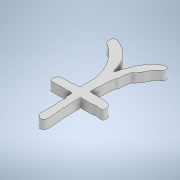
# Autodesk Inventor part: asterisk
Saved by Autodesk Inventor 2022.6 (Build 266554000, 554)
## iProperties
Created: 2024-11-29
Part Number: asterisk
Material: Generic
Document SubType Name: Modeling
Designer: Dragos Macovei
Density: 1 g/cm^3
Appearance: Default
Author: Dragos Macovei
Autodesk Inventor part; units mm, degrees
ref_plane "YZ Plane" through (0, 0, 0) normal (1, 0, 0) x (0, 1, 0)
ref_plane "XZ Plane" through (0, 0, 0) normal (0, 1, 0) x (-1, 0, 0)
ref_plane "XY Plane" through (0, 0, 0) normal (0, 0, 1) x (1, 0, 0)
sketch "Sketch1" plane through (0, 0, 0) normal (0, 1, 0) x (-1, 0, 0)
  line L0 (0, 0) -> (40, 0)
  line L1 (40, 0) -> (40, 40)
  line L2 (40, 40) -> (0, 40)
  line L3 (0, 40) -> (0, 0)
  line L4 (-196.3315, 239.7568) -> (210.0685, 239.7568) construction
  line L5 (210.0685, 239.7568) -> (210.0685, -302.1099) construction
  line L6 (210.0685, -302.1099) -> (-196.3315, -302.1099) construction
  line L7 (-196.3315, -302.1099) -> (-196.3315, 239.7568) construction
  spline S0 degree 5 poles (20.2281, 27.3819) (20.2569, 27.204) (20.2549, 26.8723) (20.134, 26.258) (20.1988, 25.9402) (20.624, 25.3677) (20.8566, 25.5249) (22.1402, 25.6276) (22.1374, 25.5328) (23.2908, 25.585) (23.6528, 25.43) (24.9068, 25.6468) (25.0732, 25.5218) (26.0735, 25.6479) (26.7605, 25.418) (27.4178, 25.7195) (27.6592, 25.3157) (27.8745, 24.8663) (27.9029, 24.2265) (27.5396, 23.4329) (27.123, 22.9859) (26.2982, 22.585) (25.8641, 22.9911) (24.6164, 22.6411) (24.2692, 22.8677) (23.501, 22.8137) (23.173, 22.7419) (21.6956, 22.4064) (21.6055, 22.7926) (20.1295, 22.4021) (21.1477, 21.1629) (20.6367, 20.4244) (20.7369, 18.6844) (20.8421, 18.3965) (20.7675, 16.6239) (21.1918, 16.2838) (21.3546, 14.7956) (21.8177, 14.0398) (22.0249, 12.759) (22.879, 11.999) (23.0894, 10.8923) (24.5043, 9.4106) (24.6383, 9.1741) (25.697, 7.9506) (26.2305, 7.4611) (26.9373, 6.6722) (27.6755, 6.2368) (28.2347, 5.9023) (28.9131, 5.4341) (29.3549, 5.1414) (29.401, 4.182) (29.338, 2.8435) (28.7401, 2.938) (27.7646, 2.6447) (27.5697, 3.1148) (26.9975, 3.3775) (26.2713, 3.4322) (26.1961, 3.6335) (25.4895, 4.1035) (25.3274, 4.0249) (24.6635, 4.7365) (24.3187, 4.6533) (23.6375, 5.2769) (23.5581, 5.6382) (22.7165, 6.1613) (22.6355, 6.5113) (21.9199, 6.8836) (21.8943, 7.4091) (21.3956, 7.9206) (21.3458, 8.3927) (20.9019, 8.991) (20.5693, 9.7122) (20.5501, 10.0411) (19.9364, 10.9466) (20.1159, 11.2294) (19.8317, 11.6297) (19.8411, 11.9953) (19.8532, 12.3537) (19.4882, 12.5146) (19.194, 12.072) (19.0966, 11.5108) (18.7825, 9.7025) (17.5682, 8.2623) (17.9054, 7.6693) (17.2705, 6.4082) (16.9669, 6.6229) (15.9508, 3.9967) (15.5021, 4.5029) (15.5187, 3.5212) (14.0905, 3.4108) (14.4439, 2.8232) (13.1534, 2.6958) (13.3925, 2.2878) (12.3471, 2.4244) (12.1262, 2.0127) (11.5009, 2.6744) (11.5881, 2.8407) (11.4434, 3.5926) (11.5846, 3.8117) (12.0443, 4.3221) (12.4856, 4.3681) (13.1431, 5.2994) (13.3385, 5.2237) (13.904, 6.3946) (14.2262, 7.085) (14.6864, 7.9895) (15.408, 8.4489) (15.5208, 9.5486) (16.5448, 9.489) (16.3687, 10.3446) (16.7009, 11.0947) (16.8321, 11.9735) (16.8069, 12.7968) (16.7762, 13.9207) (17.5294, 14.1797) (17.1249, 15.2812) (17.8431, 16.4185) (17.3602, 17.8771) (17.6668, 19.3644) (17.7503, 19.7363) (17.7277, 21.2778) (17.7746, 21.6575) (17.7621, 22.5836) (17.2166, 21.8598) (16.3217, 22.5022) (16.1361, 22.1284) (15.5326, 22.3347) (15.0782, 22.2459) (14.4673, 22.2409) (13.8289, 22.2946) (13.217, 22.283) (12.6504, 22.3687) (12.2721, 22.3558) (11.6957, 22.4418) (11.29, 22.5947) (10.8897, 22.9545) (10.5951, 23.1648) (10.1899, 23.6221) (10.1568, 24.2264) (10.2703, 24.5188) (10.0556, 25.317) (10.9444, 25.3035) (11.3109, 25.529) (12.24, 25.157) (13.047, 25.0781) (13.4217, 25.4312) (14.3351, 25.3205) (14.6439, 25.4533) (15.6247, 25.4451) (16.333, 25.3555) (16.9826, 25.5786) (17.8706, 25.1233) (17.5778, 25.9282) (17.6271, 26.571) (17.6972, 27.6801) (17.5119, 28.2924) (17.5903, 29.2013) (17.5123, 29.8826) (17.4935, 30.751) (17.5747, 32.0925) (17.2728, 32.1531) (17.4079, 33.4982) (17.271, 33.8972) (17.0965, 34.9435) (17.3021, 35.6483) (16.9283, 36.0539) (17.1812, 36.9191) (17.1135, 37.5927) (17.662, 37.9269) (17.9732, 38.1164) (18.6653, 38.3873) (18.7158, 37.6968) (19.2912, 37.486) (19.7103, 37.5451) (19.7738, 36.726) (19.9154, 36.2269) (19.8471, 34.3604) (19.8424, 33.7251) (19.6141, 31.1217) (20.4021, 30.6965) (19.6151, 28.1403) (20.047, 27.9061) (20.1923, 27.6029) (20.2281, 27.3819) knots 0 0 0 0 0 0 0.006822 0.010789 0.016049 0.020854 0.025832 0.031113 0.036873 0.042272 0.048016 0.05382 0.059393 0.064443 0.069443 0.074258 0.079073 0.084102 0.08948 0.095068 0.100968 0.106627 0.112101 0.117494 0.123209 0.128587 0.134095 0.139902 0.146101 0.152454 0.159003 0.165913 0.172773 0.179651 0.186334 0.19322 0.200017 0.207151 0.214553 0.221755 0.229012 0.236195 0.243157 0.249633 0.256028 0.262055 0.26774 0.273408 0.279255 0.285053 0.290881 0.296629 0.302123 0.307232 0.312077 0.3168 0.321442 0.326114 0.330747 0.335687 0.340634 0.345934 0.351094 0.356315 0.36142 0.366531 0.371441 0.376541 0.381753 0.387018 0.39248 0.397786 0.402788 0.407462 0.411797 0.415501 0.419062 0.422732 0.427418 0.433305 0.439817 0.446827 0.454047 0.461339 0.467524 0.473502 0.479619 0.485504 0.490638 0.495749 0.500948 0.505749 0.510597 0.515091 0.519803 0.524224 0.528692 0.533208 0.538137 0.542965 0.548254 0.553974 0.56 0.5661 0.572535 0.578735 0.584554 0.590277 0.595993 0.601813 0.607854 0.613898 0.619875 0.626102 0.632759 0.639686 0.64684 0.654283 0.661273 0.667235 0.672555 0.677858 0.682509 0.68698 0.691677 0.696531 0.701292 0.706341 0.711459 0.716495 0.721451 0.726206 0.730794 0.735292 0.739925 0.744571 0.749167 0.753799 0.758532 0.763291 0.768367 0.773759 0.779187 0.784726 0.790187 0.795596 0.801055 0.806706 0.812154 0.8174 0.822595 0.827942 0.833302 0.838963 0.845014 0.851231 0.857421 0.863348 0.869377 0.875408 0.881386 0.887101 0.892841 0.898502 0.904111 0.909365 0.914458 0.91949 0.924251 0.92887 0.93332 0.937696 0.942277 0.947501 0.95338 0.960404 0.968319 0.976932 0.985024 0.991521 1 1 1 1 1 1
  point P0 (20.3136, 25.8438)
  point P1 (20.5822, 25.5356)
  point P2 (20.9377, 25.4961)
  point P3 (21.8779, 25.583)
  point P4 (22.3124, 25.5672)
  point P5 (23.0709, 25.5435)
  point P6 (23.8214, 25.5119)
  point P7 (24.7379, 25.5751)
  point P8 (25.2277, 25.5751)
  point P9 (26.0731, 25.5672)
  point P10 (26.9105, 25.5435)
  point P11 (27.3924, 25.5435)
  point P12 (27.6295, 25.3302)
  point P13 (27.8033, 24.9273)
  point P14 (27.8349, 24.319)
  point P15 (27.5347, 23.5368)
  point P16 (27.029, 23.0075)
  point P17 (26.3891, 22.7704)
  point P18 (25.7175, 22.8258)
  point P19 (24.6905, 22.7625)
  point P20 (24.1532, 22.81)
  point P21 (23.6397, 22.81)
  point P22 (23.063, 22.7151)
  point P23 (21.9411, 22.565)
  point P24 (21.3643, 22.6124)
  point P25 (20.7402, 22.3122)
  point P26 (20.7797, 21.4274)
  point P27 (20.7797, 20.3055)
  point P28 (20.7481, 18.915)
  point P29 (20.8034, 18.0933)
  point P30 (20.8903, 16.8767)
  point P31 (21.1194, 16.0945)
  point P32 (21.4117, 14.9805)
  point P33 (21.7515, 13.9693)
  point P34 (22.1465, 12.9185)
  point P35 (22.6995, 11.9941)
  point P36 (23.3474, 10.8249)
  point P37 (24.3466, 9.5465)
  point P38 (24.8487, 8.9487)
  point P39 (25.6497, 8.0402)
  point P40 (26.3192, 7.3468)
  point P41 (27.0365, 6.6773)
  point P42 (27.7179, 6.2111)
  point P43 (28.2917, 5.8524)
  point P44 (28.8536, 5.4698)
  point P45 (29.2123, 5.0873)
  point P46 (29.3677, 4.1429)
  point P47 (29.1405, 3.0789)
  point P48 (28.5667, 2.8517)
  point P49 (27.8494, 2.8398)
  point P50 (27.4788, 3.0789)
  point P51 (26.9169, 3.3419)
  point P52 (26.367, 3.4853)
  point P53 (26.0801, 3.6766)
  point P54 (25.6019, 3.9874)
  point P55 (25.2791, 4.1548)
  point P56 (24.7531, 4.5493)
  point P57 (24.2868, 4.7884)
  point P58 (23.7728, 5.2188)
  point P59 (23.4022, 5.6611)
  point P60 (22.8403, 6.1632)
  point P61 (22.4936, 6.5219)
  point P62 (22.0632, 6.9284)
  point P63 (21.8002, 7.3946)
  point P64 (21.5013, 7.8967)
  point P65 (21.2861, 8.3629)
  point P66 (20.9394, 8.9966)
  point P67 (20.6286, 9.6541)
  point P68 (20.4015, 10.204)
  point P69 (20.0665, 10.9668)
  point P70 (20, 11.3199)
  point P71 (19.8773, 11.6857)
  point P72 (19.8394, 12.0515)
  point P73 (19.7701, 12.31)
  point P74 (19.5998, 12.3983)
  point P75 (19.3854, 12.2848)
  point P76 (19.1773, 11.837)
  point P77 (18.6814, 10.0278)
  point P78 (17.8311, 8.2007)
  point P79 (17.6557, 7.3951)
  point P80 (17.3291, 6.7206)
  point P81 (16.883, 6.1285)
  point P82 (15.8339, 4.393)
  point P83 (15.5803, 4.1584)
  point P84 (15.2196, 3.7228)
  point P85 (14.4029, 3.2532)
  point P86 (14.0762, 2.913)
  point P87 (13.4093, 2.5931)
  point P88 (13.1371, 2.4162)
  point P89 (12.4769, 2.3005)
  point P90 (12.0278, 2.2596)
  point P91 (11.6399, 2.6067)
  point P92 (11.5446, 2.947)
  point P93 (11.5106, 3.4846)
  point P94 (11.6263, 3.8249)
  point P95 (11.9801, 4.1788)
  point P96 (12.4565, 4.4987)
  point P97 (13.035, 5.0771)
  point P98 (13.3344, 5.3902)
  point P99 (13.7856, 6.161)
  point P100 (14.2541, 7.1176)
  point P101 (14.7812, 7.9375)
  point P102 (15.3278, 8.6793)
  point P103 (15.7963, 9.3626)
  point P104 (16.2844, 9.6945)
  point P105 (16.4601, 10.2215)
  point P106 (16.6358, 11.0415)
  point P107 (16.7919, 11.9395)
  point P108 (16.8115, 12.9155)
  point P109 (16.9676, 13.7745)
  point P110 (17.2409, 14.2626)
  point P111 (17.3385, 15.0044)
  point P112 (17.5533, 16.2928)
  point P113 (17.5338, 18.0107)
  point P114 (17.6509, 19.2992)
  point P115 (17.729, 20.1386)
  point P116 (17.7485, 21.3099)
  point P117 (17.7485, 21.9541)
  point P118 (17.6339, 22.2197)
  point P119 (17.2083, 22.1561)
  point P120 (16.4008, 22.2953)
  point P121 (16.0527, 22.2536)
  point P122 (15.6072, 22.2675)
  point P123 (15.106, 22.2675)
  point P124 (14.5074, 22.2536)
  point P125 (13.8113, 22.2814)
  point P126 (13.1569, 22.3093)
  point P127 (12.6418, 22.351)
  point P128 (12.2241, 22.3789)
  point P129 (11.7229, 22.4624)
  point P130 (11.2913, 22.6434)
  point P131 (10.9154, 22.9218)
  point P132 (10.5952, 23.2003)
  point P133 (10.275, 23.6597)
  point P134 (10.1915, 24.1748)
  point P135 (10.2054, 24.5925)
  point P136 (10.275, 25.0937)
  point P137 (10.7484, 25.3304)
  point P138 (11.3331, 25.4)
  point P139 (12.2381, 25.219)
  point P140 (13.0177, 25.1912)
  point P141 (13.5467, 25.3304)
  point P142 (14.2011, 25.3721)
  point P143 (14.7023, 25.4139)
  point P144 (15.5515, 25.4278)
  point P145 (16.4008, 25.4278)
  point P146 (17.1804, 25.4139)
  point P147 (17.612, 25.4139)
  point P148 (17.6677, 25.7202)
  point P149 (17.6259, 26.4998)
  point P150 (17.6399, 27.5718)
  point P151 (17.5703, 28.3654)
  point P152 (17.5563, 29.1451)
  point P153 (17.5285, 29.869)
  point P154 (17.5146, 30.8853)
  point P155 (17.4728, 31.9156)
  point P156 (17.3753, 32.3889)
  point P157 (17.3475, 33.3078)
  point P158 (17.264, 34.0317)
  point P159 (17.1804, 34.9645)
  point P160 (17.1665, 35.6328)
  point P161 (17.0691, 36.134)
  point P162 (17.1247, 36.9415)
  point P163 (17.2918, 37.5819)
  point P164 (17.6538, 37.916)
  point P165 (18.0854, 38.1388)
  point P166 (18.5309, 38.1666)
  point P167 (18.8372, 37.7907)
  point P168 (19.2688, 37.5401)
  point P169 (19.5751, 37.4148)
  point P170 (19.7421, 37.0389)
  point P171 (19.8396, 36.3707)
  point P172 (19.8674, 34.9785)
  point P173 (19.8117, 33.5445)
  point P174 (19.8535, 31.484)
  point P175 (20, 29.7716)
  point P176 (20, 27.9617)
  dimension "d0" = 40
  dimension "d1" = 40
  constraints: 8 end point, 2 parallel, 1 horizontal, 1 perpendicular, 181 other
  measures "d0" distance of L2.end L1.end
  measures "d1" distance of L1.end L0.end
extrude "Extrusion1" add sketch "Sketch1" along normal blind 3 contours S0
body "Solid1"
